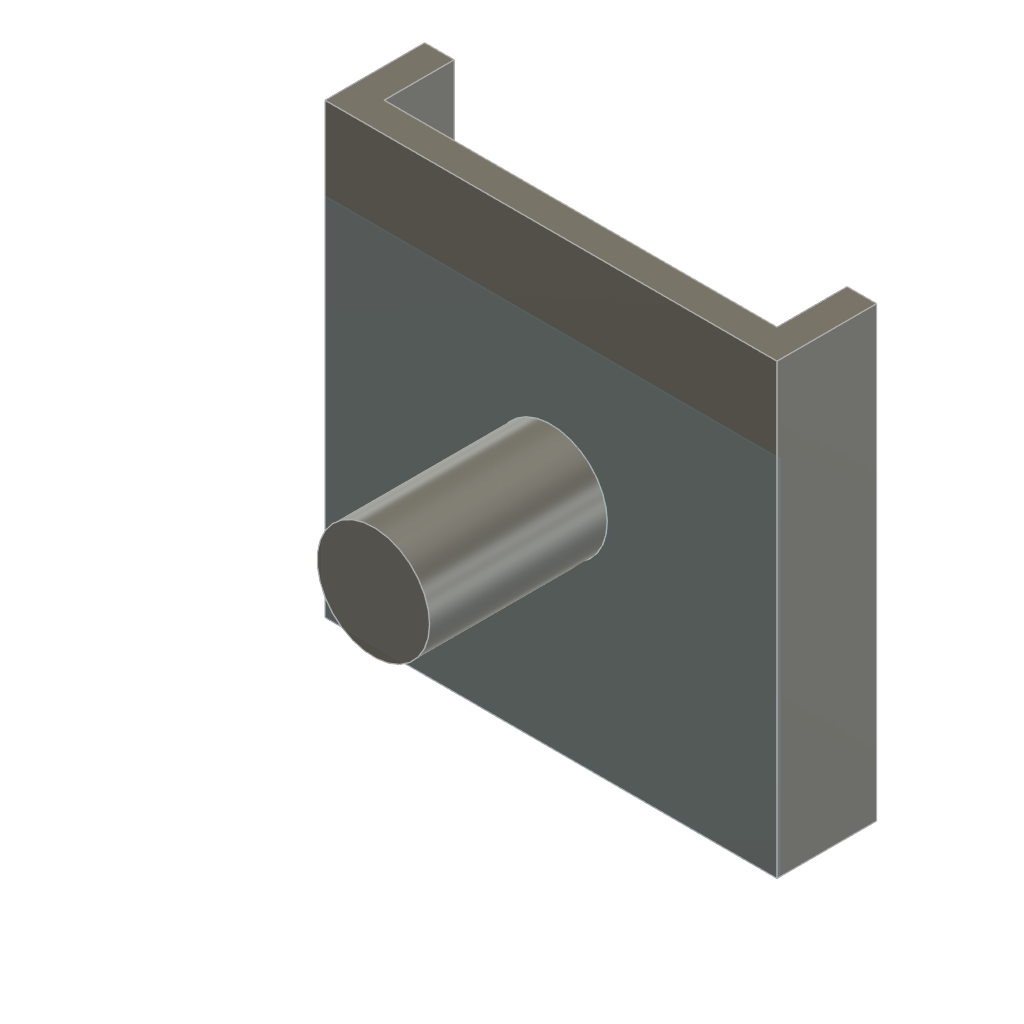
15kgHelper (Autodesk Fusion 360 design; units mm, degrees)
part number: 2026-07-20-18-30-47-544
Autodesk Fusion 360 part; units mm, degrees
sketch "Sketch1" plane through (0, 0, 0) normal (0, 1, 0) x (1, 0, 0)
  line L0 (-11.6, 2.55) -> (11.6, 2.55)
  line L1 (11.6, 2.55) -> (11.6, -2.55)
  line L2 (11.6, -2.55) -> (-11.6, -2.55)
  line L3 (-11.6, -2.55) -> (-11.6, 2.55)
  line L4 (-11.6, 2.55) -> (11.6, -2.55) construction
  line L5 (11.6, 2.55) -> (-11.6, -2.55) construction
  dimension "d1" = 23.2
  dimension "d2" = 5.1
  constraint horizontal L0
  constraint perpendicular L0 L1
  constraint parallel L0 L2
  constraint parallel L1 L3
  constraint coincident L4 origin
  constraint coincident L5 origin
  measures "d1" distance of L1.end L2.end
  measures "d2" distance of L0.end L1.end
extrude "Extrude1" add sketch "Sketch1" along normal blind 1.5
sketch "Sketch2" plane through (0, 1.5, 0) normal (0, 1, 0) x (-1, 0, 0)
  line L0 (11.6, 2.55) -> (-11.6, 2.55)
  line L1 (-11.6, 2.55) -> (-11.6, -2.55)
  line L2 (-11.6, -2.55) -> (11.6, -2.55)
  line L3 (11.6, -2.55) -> (11.6, 2.55)
  line L4 (-10.1, -2.55) -> (-10.1, 1)
  line L5 (-10.1, 1) -> (10.1, 1)
  line L6 (10.1, -2.55) -> (10.1, 1)
  constraint coincident L2 L4.start
  constraint perpendicular L0 L4
  constraint perpendicular L3 L5
  constraint coincident L2 L6.start
  constraint perpendicular L5 L6
extrude "Extrude2" add sketch "Sketch2" along normal blind 17 contours L0 L1 L2 L3 L4 L5 L6
sketch "Sketch3" plane through (0, 0, 1) normal (0, 0, -1) x (-1, 0, 0)
  line L0 (-10.1, 1.5) -> (10.1, 1.5)
  line L1 (10.1, 1.5) -> (10.1, 18.5)
  line L2 (10.1, 18.5) -> (-10.1, 18.5)
  line L3 (-10.1, 18.5) -> (-10.1, 1.5)
  circle A0 centre (0, 11.35) radius 2.85
  dimension "d12" = 5.7
  measures "d12" diameter of A0
extrude "Extrude3" add sketch "Sketch3" against normal blind 7.4 contours A0
extrude "Extrude4" cut 1 faces at (3.3667, 12.8333, 1) along direction (0, 0, 1) blind 0.05
extrude "Extrude5" add 1 faces at (0.9394, 12.2787, 8.4) along direction (0, 0, 1) blind 0.15
sketch "Sketch4" plane through (0, 0, 2.55) normal (0, 0, 1) x (1, 0, 0)
  circle A0 centre (0, 11.35) radius 2.85
  line L0 (-11.6, 0) -> (11.6, 0)
  line L1 (11.6, 0) -> (11.6, 18.5)
  line L2 (11.6, 18.5) -> (-11.6, 18.5)
  line L3 (-11.6, 18.5) -> (-11.6, 0)
extrude "Extrude6" add 1 faces at (-3.3667, 18.5, 2.05) along direction (0, 1, 0) blind 4.2
extrude "Extrude7" add 1 faces at (10.1, 8.5667, -1.35) along direction (-1, 0, 0) blind 0.15
extrude "Extrude8" cut 1 faces at (11.6, 7.5667, -0.85) along direction (-1, 0, 0) blind 0.15
extrude "Extrude9" add 1 faces at (-10.1, 8.5667, -0.15) along direction (1, 0, 0) blind 0.15
extrude "Extrude10" cut 1 faces at (-11.6, 15.1333, 0.85) along direction (1, 0, 0) blind 0.15
extrude "Extrude11" cut 1 faces at (3.3167, 0.5, -2.55) along direction (0, 0, 1) blind 0.05
extrude "Extrude12" add 1 faces at (0.9394, 12.2787, 8.55) along direction (0, 0, 1) blind 3
